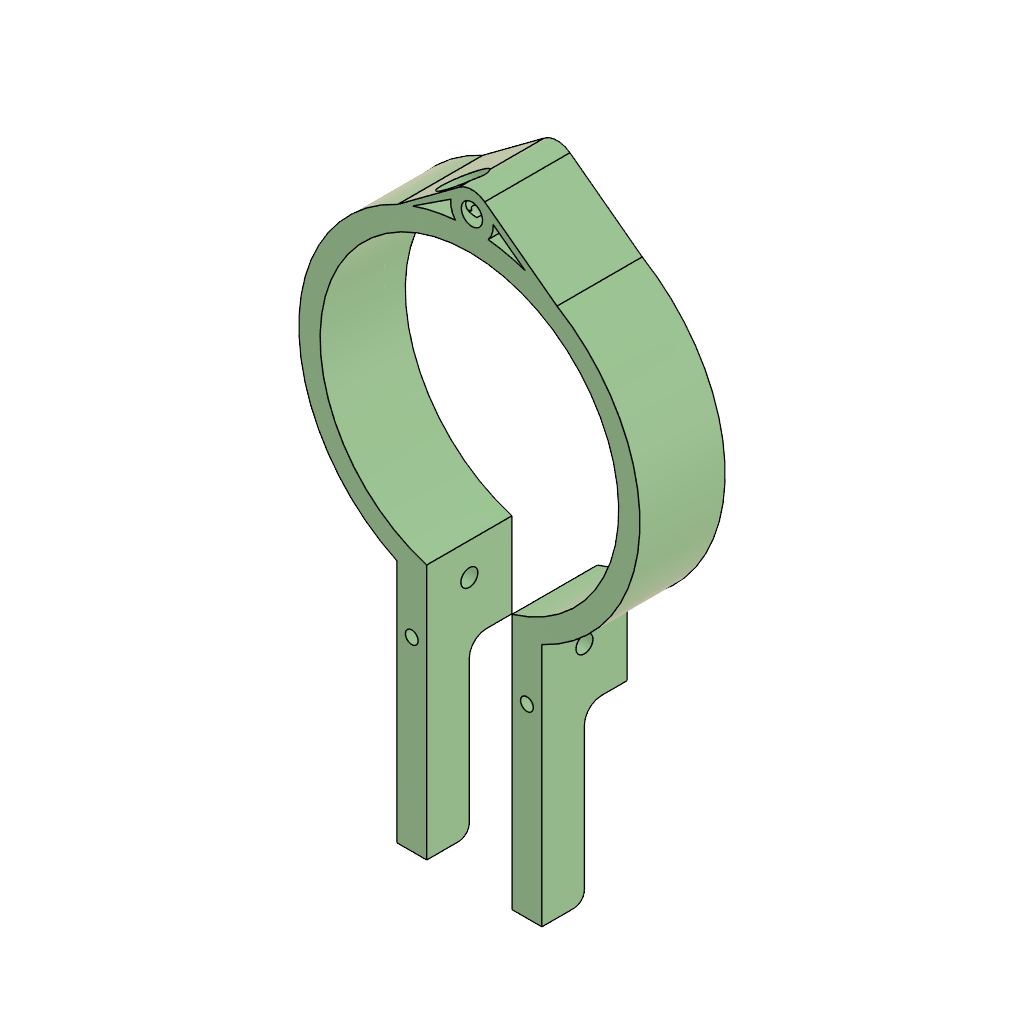
Assembled (Autodesk Fusion 360 archive; units mm, degrees)
design "BarrelHolder-dispencing"
part number: 2026-11-03-07-55-00-366
Autodesk Fusion 360 part; units mm, degrees
sketch "Sketch1" plane through (0, 0, 0) normal (0, 1, 0) x (1, 0, 0)
  circle A0 centre (3.1186, -46.0783) radius 5
  line L0 (-14.2718, -39.3886) -> (0.137, -50.092)
  line L1 (6.1136, -50.0821) -> (23.0679, -37.3997)
  line L2 (19.5172, 50.4585) -> (12.5172, 50.4585)
  line L3 (-14.4828, 50.381) -> (-7.4828, 50.381)
  line L4 (-1.8481, -46.6546) -> (-10.7537, -40.8169)
  line L5 (-14.4828, 30.381) -> (-14.4828, 50.381)
  line L6 (15.5505, -40.8996) -> (8.1032, -46.4704)
  line L7 (12.5172, 50.4585) -> (12.5172, 30.4585)
  line L8 (-7.4828, 50.381) -> (-7.4828, 30.381)
  line L9 (19.5172, 30.4585) -> (19.5172, 50.4585)
  circle A1 centre (2.5172, -3.0825) radius 35
  line L10 (12.5172, 30.4585) -> (19.5172, 30.4585)
  circle A2 centre (3.1186, -46.0783) radius 3.1
  line L11 (-7.4828, 30.381) -> (-14.4828, 30.381)
  circle A3 centre (2.5172, -3.0825) radius 40
  point P0 (2.5172, -3.0825)
  point P1 (0, -40)
  dimension "d1" = 70
  dimension "d2" = 6.2
  dimension "d3" = 43
  dimension "d4" = 80
  dimension "d5" = 10
  dimension "d6" = 7
  dimension "d7" = 20
  dimension "d8" = 7
  dimension "d9" = 20
  constraint concentric A1 A3
  constraint concentric A0 A2
  constraint coincident L1.end A3
  constraint coincident L6.start A3
  constraint coincident L6.end A0
  constraint parallel L1 L6
  constraint coincident L4.start A0
  constraint coincident L4.end A3
  constraint coincident L0.start A3
  constraint coincident L0.end A0
  constraint tangent A0 L0
  constraint coincident L1.start A0
  constraint tangent A0 L1
  constraint coincident P0 A1.centre
  constraint coincident L7.end A1
  measures "d1" diameter of A1
  measures "d2" diameter of A2
  measures "d3" distance of A0.centre P0
  measures "d4" diameter of A3
  measures "d5" diameter of A0
  measures "d6" distance of L7.end L9.start
  measures "d7" distance of L2.end L7.end
  measures "d8" distance of L8.end L5.start
  measures "d9" distance of L8.end L3.end
extrude "Extrude1" add sketch "Sketch1" against normal blind 20 contours A0 A2 A3 | A0 L0 L4 A3 | A0 L5 L9 A1 L10 L11 A3 | A0 A2 A3 | A0 L1 L6 A3 | L5 L8 A1 L11 A3 | L3 L5 L8 A3 | L2 L7 L9 A3 | L7 L9 L10 A3
sketch "Sketch2" plane through (-23.93, 0, 32.214) normal (-0.596317, 0, 0.802749) x (0, -1, 0)
  line L0 (0, 29.9807) -> (0, 12.0314)
  line L1 (0, 12.0314) -> (20, 12.0314)
  line L2 (20, 12.0314) -> (20, 29.9807)
  line L3 (20, 29.9807) -> (0, 29.9807)
  circle A0 through (17.5, 20.4434, 3.6513) (13.75, 21.835, 5.3099) (13.75, 19.0517, 1.9928)
  circle A1 through (19, 20.4434, 3.6513) (13, 22.67, 6.305) (13, 18.2167, 0.9977)
  dimension "d12" = 5
  dimension "d13" = 8
extrude "Extrude2" cut sketch "Sketch2" along normal blind 9 contours A0 | A1 in plane through (-10.6398, 0, 31.426) normal (0.998247, 0, -0.059191)
extrude "Extrude3" cut sketch "Sketch2" along normal blind 11 contours A0 | A1 in plane through (-10.6398, 0, 31.426) normal (0.998247, 0, -0.059191)
sketch "Sketch3" plane through (0, -20, 0) normal (0, -1, 0) x (1, 0, 0)
  arc A0 (-1.8481, 46.6546) -> (-0.779, 42.9465) centre (3.1186, 46.0783) ccw
  arc A1 (-0.779, 42.9465) -> (-10.7537, 40.8169) centre (2.5172, 3.0825) ccw
  line L0 (-10.7537, 40.8169) -> (-1.8481, 46.6546)
  arc A2 (6.9271, 42.8387) -> (8.1032, 46.4704) centre (3.1186, 46.0783) ccw
  line L1 (8.1032, 46.4704) -> (15.5505, 40.8996)
  arc A3 (15.5505, 40.8996) -> (6.9271, 42.8387) centre (2.5172, 3.0825) ccw
  circle A4 centre (3.1186, 46.0783) radius 3.1
  line L2 (-14.4828, -33.1252) -> (-14.4828, -50.381)
  line L3 (-14.4828, -50.381) -> (-7.4828, -50.381)
  line L4 (-7.4828, -50.381) -> (-7.4828, -30.4585)
  arc A5 (12.5172, -30.4585) -> (-7.4828, -30.4585) centre (2.5172, 3.0825) ccw
  line L5 (12.5172, -30.4585) -> (12.5172, -50.4585)
  line L6 (12.5172, -50.4585) -> (19.5172, -50.4585)
  line L7 (19.5172, -50.4585) -> (19.5172, -33.1252)
  arc A6 (19.5172, -33.1252) -> (23.0679, 37.3997) centre (2.5172, 3.0825) ccw
  line L8 (23.0679, 37.3997) -> (6.1136, 50.0821)
  arc A7 (6.1136, 50.0821) -> (0.137, 50.092) centre (3.1186, 46.0783) ccw
  line L9 (0.137, 50.092) -> (-14.2718, 39.3886)
  arc A8 (-14.2718, 39.3886) -> (-14.4828, -33.1252) centre (2.5172, 3.0825) ccw
  circle A9 centre (3.1186, 46.0783) radius 2.5
  circle A10 centre (3.1186, 46.0783) radius 3.1
  dimension "d18" = 5
  constraint concentric A0 A9
  constraint concentric A9 A10
  measures "d18" diameter of A9
extrude "Extrude4" add sketch "Sketch3" against normal blind 10.5 contours A4 A10
extrude "Extrude5" cut sketch "Sketch2" along normal blind 12 contours A0 | A1 in plane through (-10.6398, 0, 31.426) normal (0.998247, 0, -0.059191)
sketch "Sketch4" plane through (-14.4828, 0, 0) normal (-1, 0, 0) x (0, -1, 0)
  line L0 (0, -33.1252) -> (0, -50.381)
  line L1 (0, -50.381) -> (20, -50.381)
  line L2 (20, -50.381) -> (20, -33.1252)
  line L3 (20, -33.1252) -> (0, -33.1252)
  circle A0 centre (10, -38) radius 2
  dimension "d23" = 4
  measures "d23" diameter of A0
extrude "Extrude6" cut sketch "Sketch4" against normal blind 56 contours A0
sketch "Sketch5" plane through (0, -20, 0) normal (0, -1, 0) x (1, 0, 0)
  circle A0 centre (3.1186, 46.0783) radius 2.5
  arc A1 (-1.8481, 46.6546) -> (-0.779, 42.9465) centre (3.1186, 46.0783) ccw
  arc A2 (-0.779, 42.9465) -> (-10.7537, 40.8169) centre (2.5172, 3.0825) ccw
  line L0 (-10.7537, 40.8169) -> (-1.8481, 46.6546)
  arc A3 (6.9271, 42.8387) -> (8.1032, 46.4704) centre (3.1186, 46.0783) ccw
  line L1 (8.1032, 46.4704) -> (15.5505, 40.8996)
  arc A4 (15.5505, 40.8996) -> (6.9271, 42.8387) centre (2.5172, 3.0825) ccw
  line L2 (-14.4828, -33.1252) -> (-14.4828, -50.381)
  line L3 (-14.4828, -50.381) -> (-7.4828, -50.381)
  line L4 (-7.4828, -50.381) -> (-7.4828, -30.4585)
  arc A5 (12.5172, -30.4585) -> (-7.4828, -30.4585) centre (2.5172, 3.0825) ccw
  line L5 (12.5172, -30.4585) -> (12.5172, -50.4585)
  line L6 (12.5172, -50.4585) -> (19.5172, -50.4585)
  line L7 (19.5172, -50.4585) -> (19.5172, -33.1252)
  arc A6 (19.5172, -33.1252) -> (23.0679, 37.3997) centre (2.5172, 3.0825) ccw
  line L8 (23.0679, 37.3997) -> (6.1136, 50.0821)
  arc A7 (6.1136, 50.0821) -> (0.137, 50.092) centre (3.1186, 46.0783) ccw
  line L9 (0.137, 50.092) -> (-14.2718, 39.3886)
  arc A8 (-14.2718, 39.3886) -> (-14.4828, -33.1252) centre (2.5172, 3.0825) ccw
  circle A9 centre (-10.9828, -46.881) radius 1.5
  circle A10 centre (16.0172, -46.9585) radius 1.5
  dimension "d26" = 3
  dimension "d27" = 3
  dimension "d28" = 3.5
  dimension "d29" = 3.5
  dimension "d30" = 3.5
  dimension "d31" = 3.5
  measures "d26" diameter of A9
  measures "d27" diameter of A10
  measures "d28" distance of L3 A9.centre
  measures "d29" distance of L2 A9.centre
  measures "d30" distance of L5 A10.centre
  measures "d31" distance of L6 A10.centre
extrude "Extrude7" cut sketch "Sketch5" against normal blind 65 contours A9 | A10
sketch "Sketch6" plane through (0, 0, -50.4585) normal (0, 0, -1) x (1, 0, 0)
  line L0 (12.5172, 0) -> (19.5172, 0)
  line L1 (19.5172, 0) -> (19.5172, 20)
  line L2 (19.5172, 20) -> (12.5172, 20)
  line L3 (12.5172, 20) -> (12.5172, 0)
  line L4 (12.5172, 10) -> (19.5172, 10)
  line L5 (19.5172, 10) -> (19.5172, 20)
  line L6 (19.5172, 20) -> (12.5172, 20)
  line L7 (12.5172, 20) -> (12.5172, 10)
  constraint horizontal L4
  constraint vertical L5
  constraint horizontal L6
  constraint vertical L7
  constraint coincident L1.end L2.start
  constraint midpoint L3 L4.start
extrude "Extrude8" add sketch "Sketch6" along normal blind 40 contours L1 L2 L3 L4 L5 L6 L7
sketch "Sketch7" plane through (0, 0, -50.381) normal (0, 0, -1) x (1, 0, 0)
  line L0 (-14.4828, 0) -> (-7.4828, 0)
  line L1 (-7.4828, 0) -> (-7.4828, 20)
  line L2 (-7.4828, 20) -> (-14.4828, 20)
  line L3 (-14.4828, 20) -> (-14.4828, 0)
  line L4 (-14.4828, 10) -> (-7.4828, 10)
  line L5 (-7.4828, 10) -> (-7.4828, 20)
  line L6 (-7.4828, 20) -> (-14.4828, 20)
  line L7 (-14.4828, 20) -> (-14.4828, 10)
  constraint horizontal L4
  constraint vertical L5
  constraint horizontal L6
  constraint vertical L7
  constraint coincident L1.end L2.start
  constraint midpoint L3 L4.start
extrude "Extrude9" add sketch "Sketch7" along normal blind 40 contours L1 L2 L3 L4 L5 L6 L7
fillet "Fillet1" radius 4 2 edges at (-10.9828, -10, -50.381) (16.0172, -10, -50.4585)
fillet "Fillet2" radius 2.5 2 edges at (16.0172, -10, -90.4585) (-10.9828, -10, -90.381)

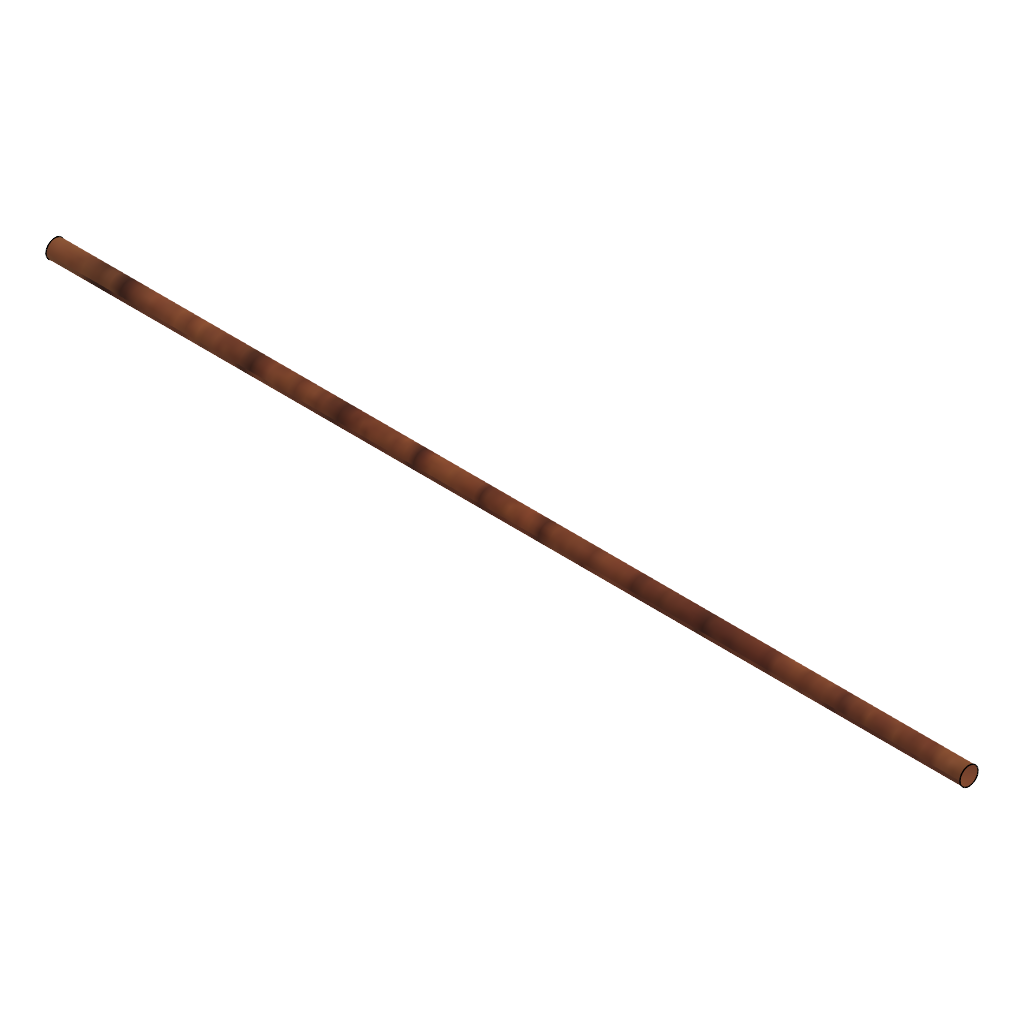
design "Wooden Spoke UnderCan"
part number: 2026-11-03-09-25-07-605
Autodesk Fusion 360 part; units mm, degrees
sketch "Sketch1" plane through (0, 0, 0) normal (1, 0, 0) x (0, 1, 0)
  circle A0 centre (0, 0) radius 1.5
  dimension "d1" = 3
  constraint coincident A0.centre origin
  measures "d1" diameter of A0
extrude "Extrude1" add sketch "Sketch1" along normal blind 300
extrude "Extrude2" cut 1 faces at (0, 0.567, -0.5383) along direction (1, 0, 0) blind 150

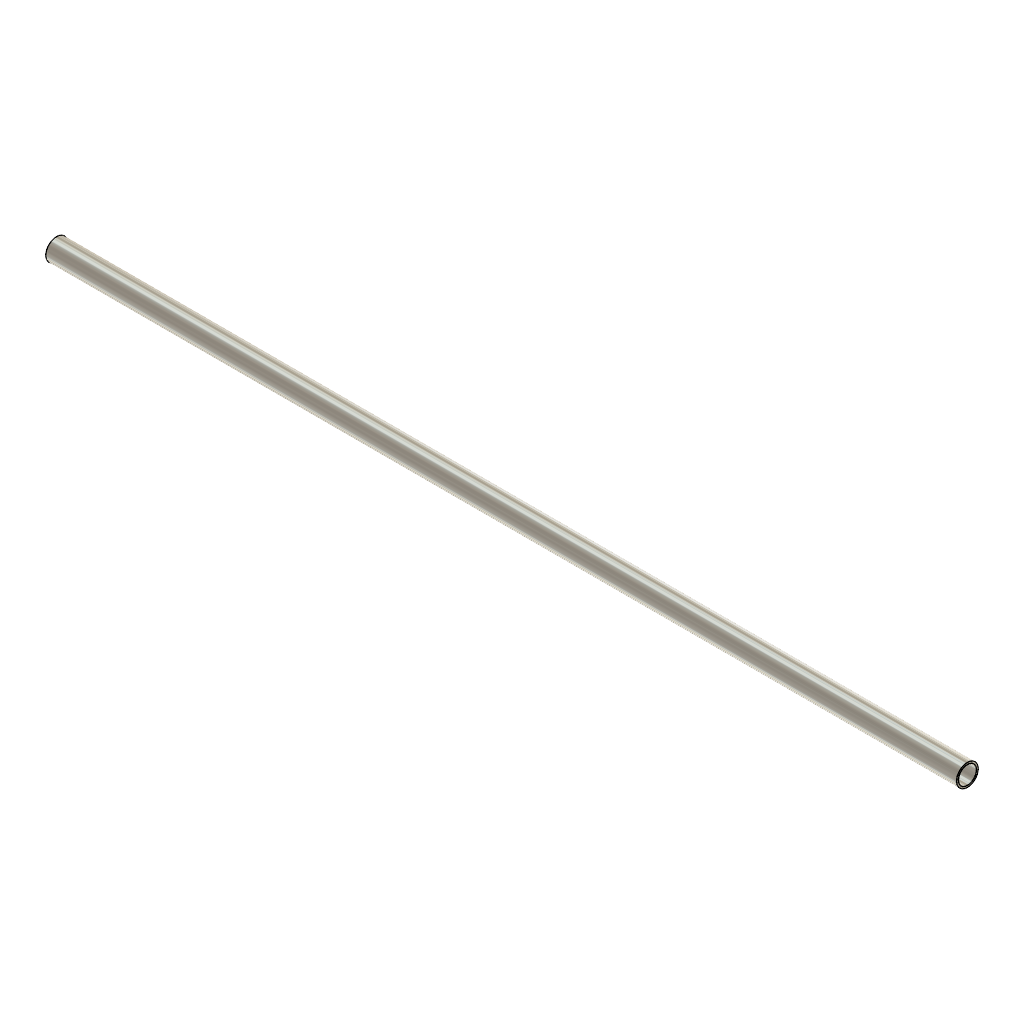
design "Barrel"
part number: 2026-11-02-22-59-22-936
Autodesk Fusion 360 part; units mm, degrees
sketch "Sketch1" plane through (0, 0, 0) normal (1, 0, 0) x (0, 1, 0)
  circle A0 centre (0, 0) radius 2.5
  circle A1 centre (0, 0) radius 3
  dimension "d1" = 5
  dimension "d2" = 6
  constraint coincident A0.centre A1.centre
  measures "d1" diameter of A0
  measures "d2" diameter of A1
extrude "Extrude1" add sketch "Sketch1" along normal blind 250

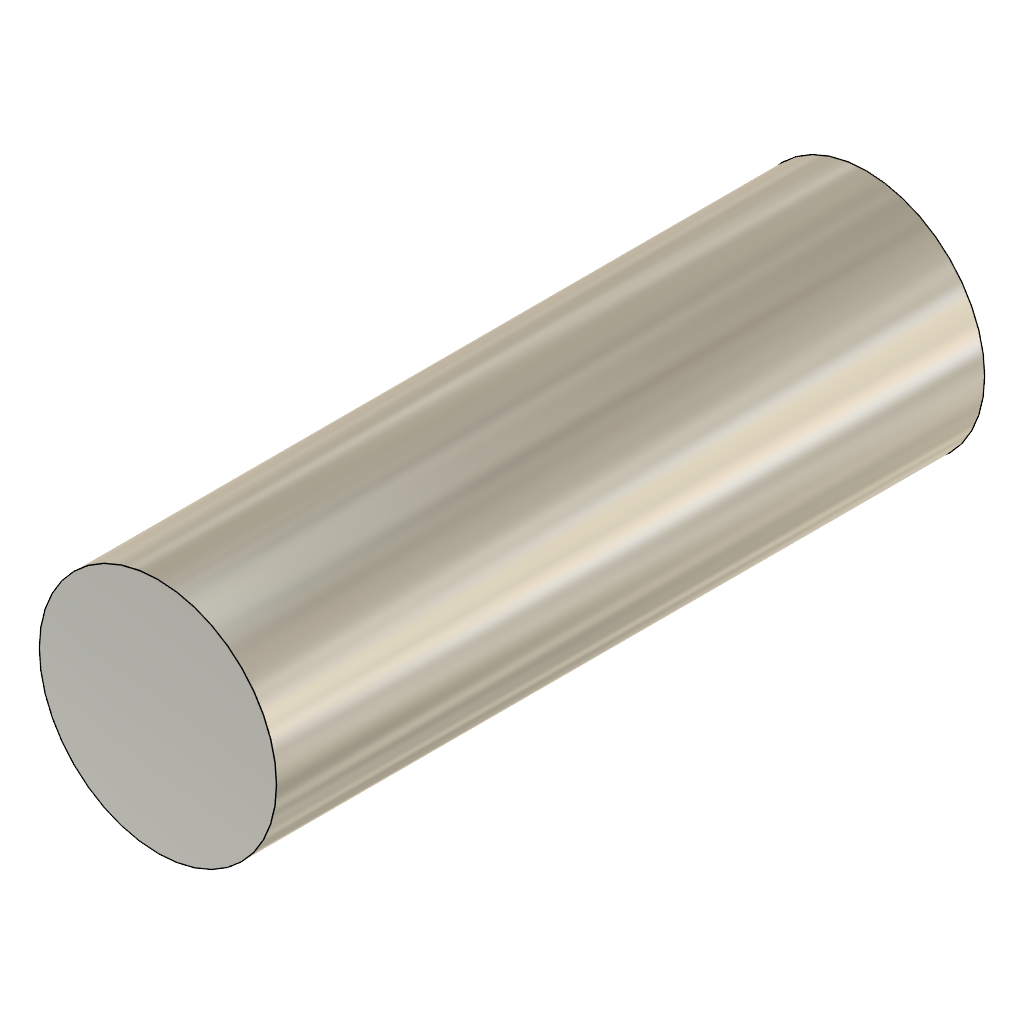
design "AirCAN"
part number: 2026-11-02-22-48-09-711
Autodesk Fusion 360 part; units mm, degrees
sketch "Sketch1" plane through (0, 0, 0) normal (0, 1, 0) x (1, 0, 0)
  circle A0 centre (0, 0) radius 32.5
  circle A1 centre (0, 0) radius 33.5
  dimension "d1" = 65
  dimension "d2" = 67
  constraint coincident A0.centre A1.centre
  constraint concentric A0 A1
  measures "d1" diameter of A0
  measures "d2" diameter of A1
extrude "Extrude1" add sketch "Sketch1" along normal blind 200
sketch "Sketch2" plane through (0, 0, 0) normal (0, 1, 0) x (1, 0, 0)
  circle A0 centre (0, 0) radius 32.7154
  constraint coincident A0.centre origin
extrude "Extrude2" add sketch "Sketch2" along normal blind 10
sketch "Sketch3" plane through (0, 200, 0) normal (0, 1, 0) x (-1, 0, 0)
  circle A0 centre (0, 0) radius 32.5
  circle A1 centre (0, 0) radius 33.5
  circle A2 centre (0, 0) radius 32.5
  circle A3 centre (0, 0) radius 6.85
  dimension "d7" = 13.7
  constraint coincident A0.centre A1.centre
  measures "d7" diameter of A3
extrude "Extrude3" add sketch "Sketch3" against normal blind 5 contours A0 A2

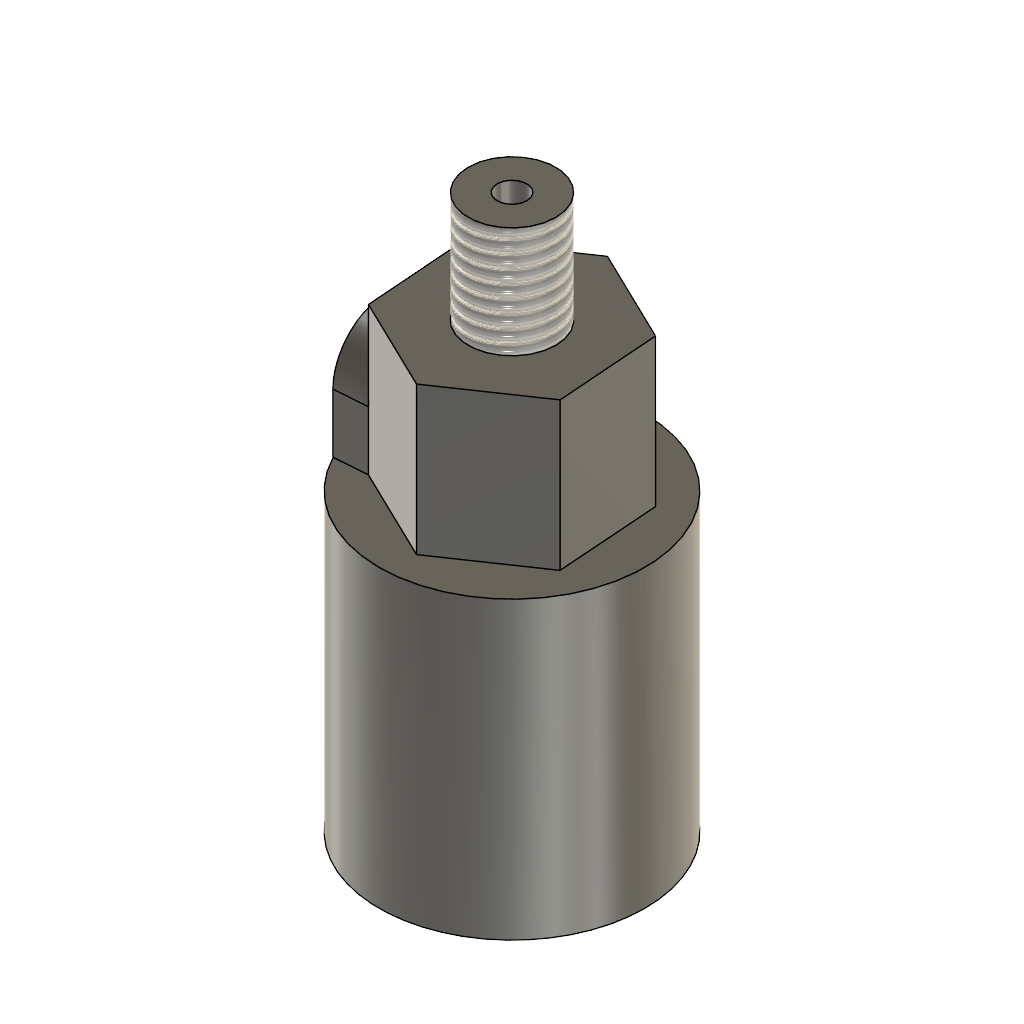
design "solnoid valve"
part number: 2026-11-02-13-06-45-913
Autodesk Fusion 360 part; units mm, degrees
sketch "Sketch1" plane through (0, 0, 0) normal (0, 0, 1) x (1, 0, 0)
  circle A0 centre (0, 0) radius 18
  dimension "d1" = 36
  constraint coincident A0.centre origin
  measures "d1" diameter of A0
extrude "Extrude1" add sketch "Sketch1" along normal blind 40
sketch "Sketch2" plane through (0, 0, 40) normal (0, 0, 1) x (-1, 0, 0)
  circle A0 centre (0, 0) radius 18
  line L0 (-12.6063, 6.0895) -> (-11.5768, -7.8726)
  line L1 (-11.5768, -7.8726) -> (1.0295, -13.9621)
  line L2 (1.0295, -13.9621) -> (12.6063, -6.0895)
  line L3 (12.6063, -6.0895) -> (11.5768, 7.8726)
  line L4 (11.5768, 7.8726) -> (-1.0295, 13.9621)
  line L5 (-1.0295, 13.9621) -> (-12.6063, 6.0895)
  dimension "d4" = 14
  constraint coincident A0.centre origin
  measures "d4" distance of L0.start A0.centre
extrude "Extrude2" add sketch "Sketch2" along normal blind 20 contours L0 L1 L2 L3 L4 L5
sketch "Sketch3" plane through (0, 0, 60) normal (0, 0, 1) x (-1, 0, 0)
  line L0 (-1.0295, 13.9621) -> (-12.6063, 6.0895)
  line L1 (-12.6063, 6.0895) -> (-11.5768, -7.8726)
  line L2 (-11.5768, -7.8726) -> (1.0295, -13.9621)
  line L3 (1.0295, -13.9621) -> (12.6063, -6.0895)
  line L4 (12.6063, -6.0895) -> (11.5768, 7.8726)
  line L5 (11.5768, 7.8726) -> (-1.0295, 13.9621)
  circle A0 centre (0, 0) radius 6
  circle A1 centre (0, 0) radius 2
  dimension "d7" = 12
  dimension "d8" = 4
  constraint coincident A0.centre A1.centre
  constraint concentric A0 A1
  measures "d7" diameter of A0
  measures "d8" diameter of A1
extrude "Extrude3" add sketch "Sketch3" along normal blind 15 contours A0
thread "Thread1" "ISO Metric profile 12.0 M12x1.75 M12x1.75 6g" major diameter 11.8335 minor diameter 9.8365 pitch 1.75 angle 60 resizes the face on face at (-5.9702, 0.5974, 70)
sketch "Sketch4" plane through (-12.0915, -0.8916, 0) normal (-0.997293, -0.073536, 0) x (0.073536, -0.997293, 0)
  line L0 (-7, 40) -> (7, 40)
  line L1 (7, 40) -> (7, 60)
  line L2 (7, 60) -> (-7, 60)
  line L3 (-7, 60) -> (-7, 40)
  line L4 (-7, 40) -> (7, 40)
  line L5 (7, 40) -> (7, 48)
  line L6 (7, 48) -> (-7, 48)
  line L7 (-7, 48) -> (-7, 40)
  circle A0 centre (0, 48) radius 7
  dimension "d13" = 14
  constraint horizontal L4
  constraint vertical L5
  constraint horizontal L6
  constraint vertical L7
  constraint coincident L1 L5.end
  constraint coincident L0.start L3.end
  constraint midpoint L6 A0.centre
  measures "d13" diameter of A0
extrude "Extrude4" add sketch "Sketch4" along normal blind 4.5 contours L0 L1 L3 L4 L5 L7 A0 | L6 A0 | L6 A0
sketch "Sketch6" plane through (-16.5793, -1.2225, 0) normal (-0.997293, -0.073536, 0) x (0.073536, -0.997293, 0)
  arc A0 (7, 48) -> (-7, 48) centre (0, 48) ccw
  line L0 (-7, 48) -> (-7, 40)
  line L1 (-7, 40) -> (-6.9015, 40)
  line L2 (-6.9015, 40) -> (6.9015, 40)
  line L3 (6.9015, 40) -> (7, 40)
  line L4 (7, 40) -> (7, 48)
  circle A1 centre (0, 46) radius 5.075
  dimension "d17" = 10.15
  measures "d17" diameter of A1
extrude "Extrude5" cut sketch "Sketch6" against normal blind 14 contours A1
sketch "Sketch5" plane through (-16.5793, -1.2225, 0) normal (-0.997293, -0.073536, 0) x (0.073536, -0.997293, 0)
  arc A0 (7, 48) -> (-7, 48) centre (0, 48) ccw
  line L0 (-7, 48) -> (-7, 40)
  line L1 (-7, 40) -> (-6.9015, 40)
  line L2 (-6.9015, 40) -> (6.9015, 40)
  line L3 (6.9015, 40) -> (7, 40)
  line L4 (7, 40) -> (7, 48)
  circle A1 centre (0, 46) radius 3.175
  dimension "d16" = 6.35
  measures "d16" diameter of A1

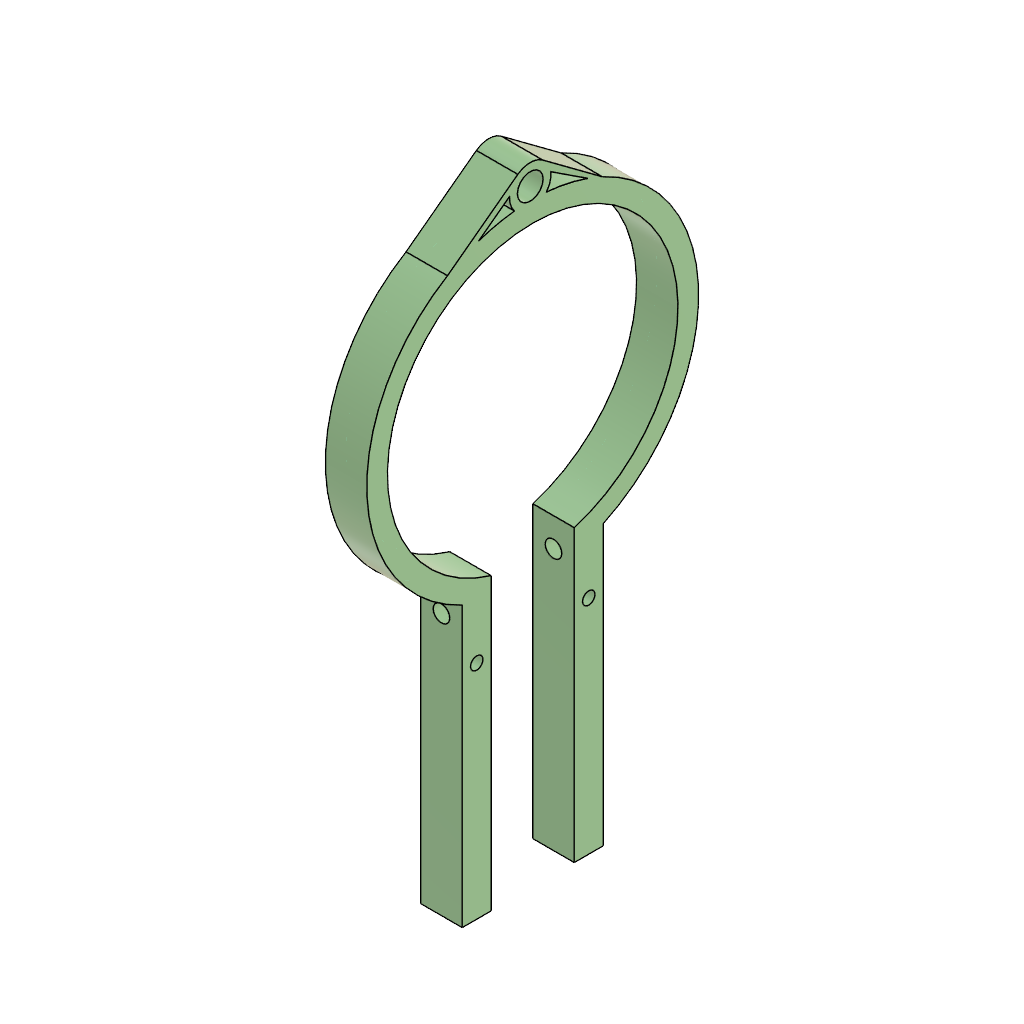
design "barrel holder"
part number: 2026-11-02-23-04-21-446
Autodesk Fusion 360 part; units mm, degrees
sketch "Sketch1" plane through (0, 0, 0) normal (1, 0, 0) x (0, 1, 0)
  circle A0 centre (-2.5172, -36.9175) radius 35
  circle A1 centre (-3.1186, 6.0783) radius 3.1
  circle A2 centre (-2.5172, -36.9175) radius 40
  circle A3 centre (-3.1186, 6.0783) radius 5
  line L0 (-6.1136, 10.0821) -> (-23.0679, -2.6003)
  line L1 (-15.5505, 0.8996) -> (-8.1032, 6.4704)
  line L2 (1.8481, 6.6546) -> (10.7537, 0.8169)
  line L3 (14.2718, -0.6114) -> (-0.137, 10.092)
  line L4 (-2.5172, -36.9175) -> (-2.5172, -103.6653)
  line L5 (-12.5172, -70.4585) -> (-19.5172, -70.4585)
  line L6 (-19.5172, -70.4585) -> (-19.5172, -90.4585)
  line L7 (-19.5172, -90.4585) -> (-12.5172, -90.4585)
  line L8 (-12.5172, -90.4585) -> (-12.5172, -70.4585)
  line L9 (7.4828, -70.381) -> (14.4828, -70.381)
  line L10 (14.4828, -70.381) -> (14.4828, -90.381)
  line L11 (14.4828, -90.381) -> (7.4828, -90.381)
  line L12 (7.4828, -90.381) -> (7.4828, -70.381)
  dimension "d1" = 70
  dimension "d2" = 6.2
  dimension "d3" = 43
  dimension "d4" = 80
  dimension "d5" = 10
  dimension "d22" = 7
  dimension "d23" = 20
  dimension "d24" = 7
  dimension "d25" = 20
  dimension "d27" = 10
  constraint concentric A0 A2
  constraint concentric A1 A3
  constraint coincident A2 L0.end
  constraint coincident A2 L1.start
  constraint coincident A3 L1.end
  constraint parallel L0 L1
  constraint coincident A3 L2.start
  constraint coincident A2 L2.end
  constraint coincident A2 L3.start
  constraint coincident A3 L3.end
  constraint tangent A3 L3
  constraint coincident A3 L0.start
  constraint tangent A3 L0
  constraint coincident A0.centre A2.centre
  constraint vertical L4
  constraint horizontal L5
  constraint vertical L6
  constraint horizontal L7
  constraint vertical L8
  constraint coincident A0 L5.start
  constraint horizontal L9
  constraint vertical L10
  constraint horizontal L11
  constraint vertical L12
  measures "d1" diameter of A0
  measures "d2" diameter of A1
  measures "d3" distance of A0.centre A1.centre
  measures "d4" diameter of A2
  measures "d5" diameter of A3
  measures "d22" distance of L5.start L5.end
  measures "d23" distance of L5.start L7.end
  measures "d24" distance of L9.start L9.end
  measures "d25" distance of L9.start L11.end
  measures "d27" distance of L4 L12
extrude "Extrude5" add sketch "Sketch1" along normal blind 10 contours A0 A2 A3 L5 L6 L9 L10 | A2 L5 L6 L8 | A0 A2 L9 L10 L12 | A2 L6 L7 L8 | A2 L10 L11 L12 | A2 A3 L0 L1 | A1 A2 A3 | A2 A3 L2 L3 | A1 A2 A3
sketch "Sketch4" plane through (0, -19.5172, 0) normal (0, -1, 0) x (1, 0, 0)
  line L0 (0, -73.1252) -> (0, -90.4585)
  line L1 (0, -90.4585) -> (10, -90.4585)
  line L2 (10, -90.4585) -> (10, -73.1252)
  line L3 (10, -73.1252) -> (0, -73.1252)
  circle A0 centre (5, -77.3604) radius 2
  dimension "d31" = 4
  measures "d31" diameter of A0
extrude "Extrude6" cut sketch "Sketch4" against normal blind 66 contours A0
sketch "Sketch5" plane through (10, 0, 0) normal (1, 0, 0) x (0, 1, 0)
  arc A0 (0.779, 2.9465) -> (1.8481, 6.6546) centre (-3.1186, 6.0783) ccw
  line L0 (1.8481, 6.6546) -> (10.7537, 0.8169)
  arc A1 (10.7537, 0.8169) -> (0.779, 2.9465) centre (-2.5172, -36.9175) ccw
  circle A2 centre (-3.1186, 6.0783) radius 3.1
  arc A3 (-6.9271, 2.8387) -> (-15.5505, 0.8996) centre (-2.5172, -36.9175) ccw
  line L1 (-15.5505, 0.8996) -> (-8.1032, 6.4704)
  arc A4 (-8.1032, 6.4704) -> (-6.9271, 2.8387) centre (-3.1186, 6.0783) ccw
  arc A5 (14.4828, -73.1252) -> (14.2718, -0.6114) centre (-2.5172, -36.9175) ccw
  line L2 (14.2718, -0.6114) -> (-0.137, 10.092)
  arc A6 (-0.137, 10.092) -> (-6.1136, 10.0821) centre (-3.1186, 6.0783) ccw
  line L3 (-6.1136, 10.0821) -> (-23.0679, -2.6003)
  arc A7 (-23.0679, -2.6003) -> (-19.5172, -73.1252) centre (-2.5172, -36.9175) ccw
  line L4 (-19.5172, -73.1252) -> (-19.5172, -90.4585)
  line L5 (-19.5172, -90.4585) -> (-12.5172, -90.4585)
  line L6 (-12.5172, -90.4585) -> (-12.5172, -70.4585)
  arc A8 (7.4828, -70.4585) -> (-12.5172, -70.4585) centre (-2.5172, -36.9175) ccw
  line L7 (7.4828, -70.4585) -> (7.4828, -90.381)
  line L8 (7.4828, -90.381) -> (14.4828, -90.381)
  line L9 (14.4828, -90.381) -> (14.4828, -73.1252)
  circle A9 centre (-16.0172, -86.9585) radius 1.5
  circle A10 centre (10.9828, -86.881) radius 1.5
  dimension "d34" = 3
  dimension "d35" = 3
  dimension "d38" = 3.5
  dimension "d39" = 3.5
  dimension "d40" = 3.5
  dimension "d41" = 3.5
  measures "d34" diameter of A9
  measures "d35" diameter of A10
  measures "d38" distance of L4 A9.centre
  measures "d39" distance of L7 A10.centre
  measures "d40" distance of L5 A9.centre
  measures "d41" distance of L8 A10.centre
extrude "Extrude7" cut sketch "Sketch5" against normal blind 22 contours A9 | A10
extrude "Extrude8" add 1 faces at (3.3333, -17.1839, -90.4585) along direction (0, 0, -1) blind 50
extrude "Extrude9" add 1 faces at (3.3333, 12.1495, -90.381) along direction (0, 0, -1) blind 50
extrude "Extrude1" [suppressed]
sketch "Sketch2" plane through (0, -11, 0) normal (0, -1, 0) x (1, 0, 0)
  line L0 (0, -73.9422) -> (0, -82.4547)
  line L1 (0, -82.4547) -> (10, -82.4547)
  line L2 (10, -82.4547) -> (10, -73.9422)
  line L3 (10, -73.9422) -> (0, -73.9422)
  circle A0 centre (5, -79) radius 1.9
  dimension "d10" = 3.8
  measures "d10" diameter of A0
extrude "Extrude2" [suppressed]
sketch "Sketch3" plane through (0, -1, 0) normal (0, 1, 0) x (-1, 0, 0)
  line L0 (0, -7.5154) -> (0, -2.9913)
  line L1 (0, -2.9913) -> (-10, -2.9913)
  line L2 (-10, -2.9913) -> (-10, -7.5154)
  line L3 (-10, -7.5154) -> (0, -7.5154)
extrude "Extrude3" [suppressed]
extrude "Extrude4" [suppressed]
equation "d3 = ( ( 75 / 2 ) * 1 mm ) + ( ( 5 / 2 ) * 1 mm ) + ( 3 mm )"
equation "a = 10 mm"
equation "d27 = a"
equation "d38 = 2 mm + 1.5 mm"

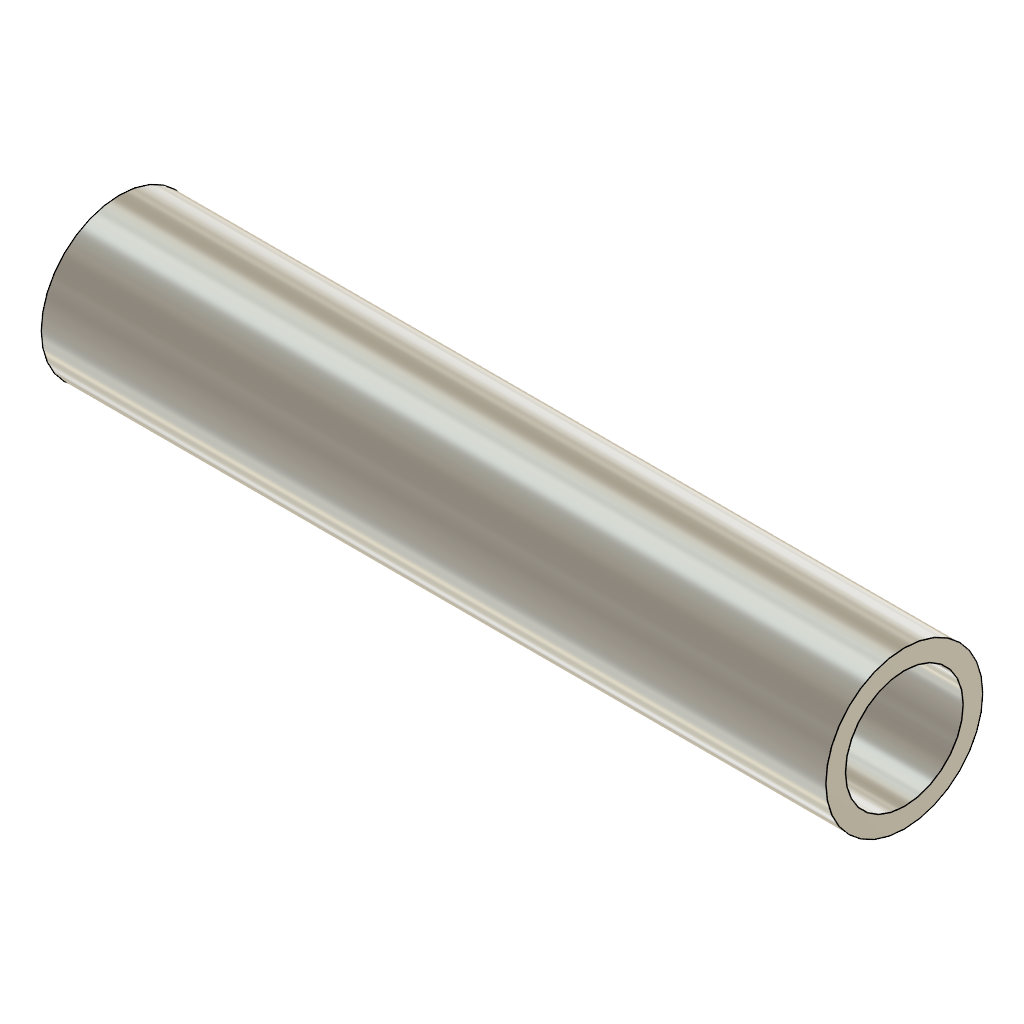
design "6mm bore_hollow"
part number: 2026-11-02-21-42-52-432
Autodesk Fusion 360 part; units mm, degrees
sketch "Sketch1" plane through (0, 0, 0) normal (1, 0, 0) x (0, 1, 0)
  circle A0 centre (0, 0) radius 3
  circle A1 centre (0, 0) radius 4
  dimension "d1" = 6
  dimension "d2" = 8
  constraint coincident A0.centre A1.centre
  constraint concentric A0 A1
  measures "d1" diameter of A0
  measures "d2" diameter of A1
extrude "Extrude1" add sketch "Sketch1" along normal blind 40

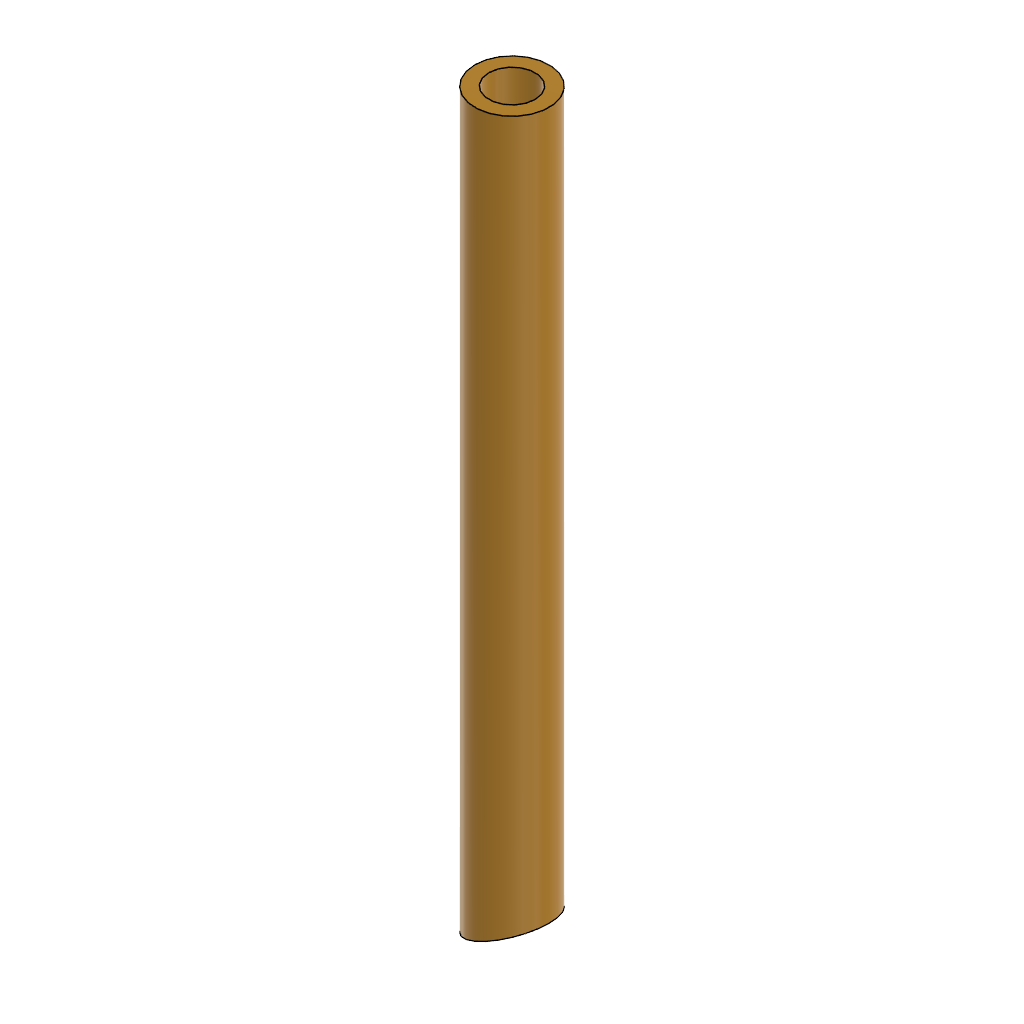
design "Ammo_MAG"
part number: 2026-11-03-08-52-14-441
Autodesk Fusion 360 part; units mm, degrees
sketch "Sketch1" plane through (0, 0, 0) normal (0, 0, 1) x (1, 0, 0)
  circle A0 centre (0, 0) radius 2.5
  circle A1 centre (0, 0) radius 4
  dimension "d1" = 5
  dimension "d2" = 8
  constraint coincident A0.centre A1.centre
  measures "d1" diameter of A0
  measures "d2" diameter of A1
extrude "Extrude1" add sketch "Sketch1" along normal blind 80
sketch "Sketch2" plane through (0, 0, 0) normal (0, 1, 0) x (1, 0, 0)
  line L0 (-5, 0, 5) -> (4.5783, -4.026, 5)
  line L1 (4.5783, -4.026, 5) -> (4.5783, 0, 5)
  line L2 (4.5783, 0, 5) -> (-5, 0, 5)
extrude "Extrude2" cut sketch "Sketch2" against normal blind 12 contours L0 L1 L2 in plane through (0, 5, 0) normal (0, 1, 0)

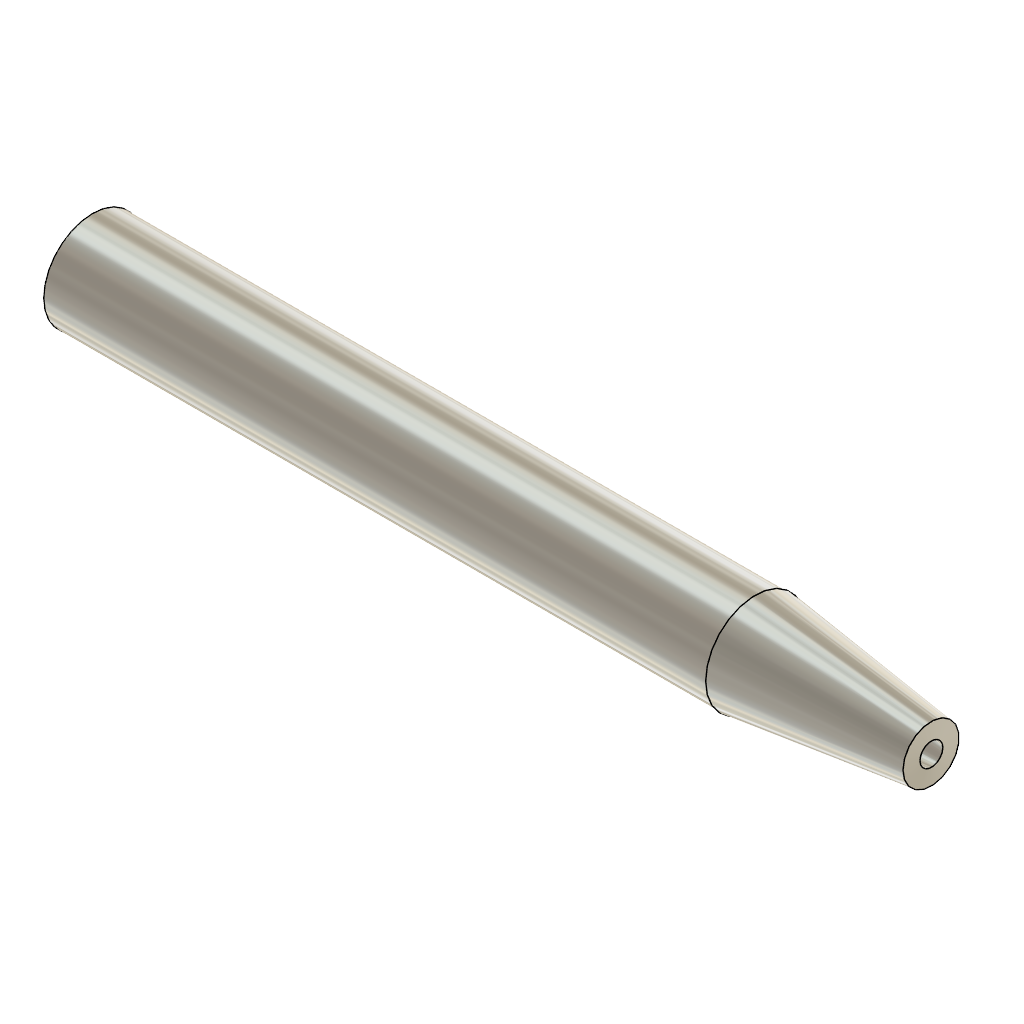
design "5.9mm bore slider"
part number: 2026-11-02-21-46-10-897
Autodesk Fusion 360 part; units mm, degrees
sketch "Sketch1" plane through (0, 0, 0) normal (1, 0, 0) x (0, 1, 0)
  circle A0 centre (0, 0) radius 2.95
  circle A1 centre (0, 0) radius 2.25
  dimension "d1" = 5.9
  dimension "d2" = 4.5
  constraint coincident A0.centre A1.centre
  measures "d1" diameter of A0
  measures "d2" diameter of A1
extrude "Extrude1" add sketch "Sketch1" along normal blind 40
sketch "Sketch2" plane through (0, 0, 0) normal (0, 0, 1) x (1, 0, 0)
  line L0 (40, 0) -> (50.6368, 0)
  line L1 (40, -3) -> (50.5997, -1.6933)
  line L2 (40, -2) -> (50.7601, -0.6735)
  line L3 (50.5997, -1.6933) -> (50.6368, 0)
  line L4 (40, -3) -> (40, -2)
  dimension "d5" = 0.6847
  constraint horizontal L0
  constraint parallel L1 L2
  constraint vertical L4
  measures "d5" distance of L0.end L2.end
revolve "Revolve1" add sketch "Sketch2" angle 360 about axis through (40, 0, 0) along (1, 0, 0)
